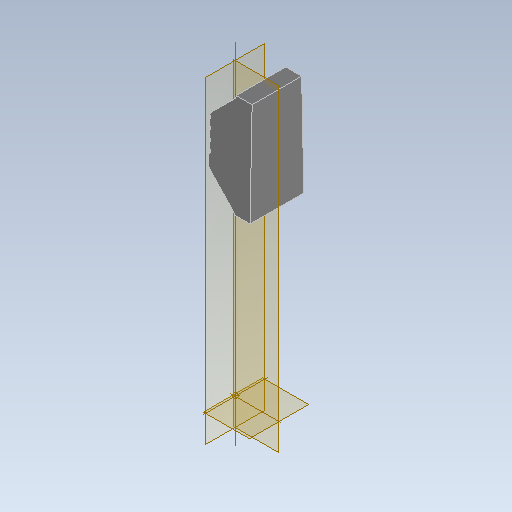
# Autodesk Inventor part: Finger_2
Saved by Autodesk Inventor 2021 (Build 250183000, 183)
## iProperties
Created: 2026-03-26
Part Number: Finger_2
Material: Generic
Document SubType Name: Modeling
Designer: Admin
Density: 1 g/cm^3
Appearance: Silicon Nitride - Polished
Mass: 13.6507 g
Surface Area: 45.9395 cm^2
Volume: 13.6507 cm^3
Author: Admin
Autodesk Inventor part; units mm, degrees
sketch "Sketch1" plane through (0, 0, 0) normal (0, 0, 1) x (1, 0, 0)
  line L0 (0, 0) -> (18, 0)
  line L1 (18, 0) -> (18, 155)
  line L2 (18, 155) -> (0, 155)
  line L3 (0, 155) -> (0, 0)
  dimension "d0" = 155
  dimension "d1" = 18
  constraints: 8 end point, 2 parallel, 1 horizontal, 1 perpendicular
  measures "d0" distance of L2.end L0.start
  measures "d1" distance of L0.start L0.end
extrude "Extrusion1" add sketch "Sketch1" along normal mid plane 25
sketch "Sketch3" plane through (0, 0, 12.5) normal (0, 0, 1) x (1, 0, 0)
  line L0 (18, 155) -> (0, 155) projected
  line L1 (0, 155) -> (0, 135)
  line L2 (0, 135) -> (12, 123)
  line L3 (12, 123) -> (0, 111)
  line L4 (0, 111) -> (0, 91)
  line L5 (0, 155) -> (0, 0) projected
  line L6 (0, 0) -> (18, 0) projected
  line L7 (18, 0) -> (18, 155) projected
  line L8 (18, 0) -> (18, 155)
  line L9 (18, 155) -> (0, 155)
  line L10 (0, 91) -> (12, 79)
  line L11 (12, 79) -> (0, 67)
  line L12 (12, 0) -> (18, 0)
  line L13 (0, 67) -> (0, 47)
  line L14 (0, 47) -> (12, 35)
  line L15 (12, 35) -> (12, 0)
  line L16 (0, 186) -> (0, -31) projected
  line L17 (-3.6, 0) -> (21.6, 0) projected
  dimension "d6" = 20
  dimension "d8" = 20
  dimension "d10" = 20
  dimension "d13" = 12
  dimension "d14" = 12
  dimension "d16" = 12
  dimension "d17" = 135
  dimension "d61" = 135
  dimension "d62" = 135
  dimension "d63" = 135
  dimension "d64" = 135
  constraints: 24 end point, 5 point on line, 4 vertical, 1 collinear, 1 perpendicular, 1 other
  measures "d6" distance of L0.end L1.end
  measures "d8" distance of L3.end L4.end
  measures "d10" distance of L11.end L13.end
  measures "d13" horizontal distance of L2.end L1.end
  measures "d14" distance from line of L5 L10.end
  measures "d16" distance from line of L14.end L13
  measures "d17" angle of L14 L5
  measures "d61" angle of L11 L5
  measures "d62" angle of L3 L5
  measures "d63" angle of L4 L10
  measures "d64" angle of L1 L2
extrude "Extrusion2" cut sketch "Sketch3" against normal through all contours L2 L3 L5 | L6 L5 L14 L15 | L10 L11 L5
sketch "Sketch4" plane through (18, 0, 12.5) normal (1, 0, 0) x (0, 0, -1)
  line L0 (0, 35) -> (25, 35) projected
  line L1 (25, 155) -> (0, 155) projected
  line L2 (2.5, 155) -> (22.5, 155)
  line L3 (25, 35) -> (22.5, 155)
  line L4 (2.5, 155) -> (0, 35)
  line L5 (12.5, -31) -> (12.5, 186) projected
  line L6 (0, 0) -> (0, 155) projected
  line L7 (25, 155) -> (25, 0) projected
  point P0 (12.5, 0)
  point P1 (12.5, 155)
  dimension "d20" = 20
  constraints: 6 end point, 3 point on line, 1 midpoint
  measures "d20" distance of L2.start L2.end
extrude "Extrusion3" cut sketch "Sketch4" against normal through all contours L6 L1 L4 | L3 L1 L7
sketch "Sketch5" plane through (12, 0, -12.5) normal (-1, 0, 0) x (0, 0, 1)
  line L0 (-12, 0) -> (37, 0) projected
  line L1 (12.5, 186) -> (12.5, -31) projected
  line L2 (0, 0) -> (0, 35) projected
  circle A0 centre (0, 20) radius 5
  line L3 (25, 0) -> (25, 35) projected
  circle A1 centre (25, 20) radius 5
  line L4 (25, 35) -> (0, 35) projected
  point P0 (12.5, 0)
  point P1 (25, 25)
  point P2 (25, 15)
  point P3 (0, 25)
  point P4 (0, 15)
  dimension "d58" = 15
  dimension "d59" = 15
  dimension "d60" = 10
  constraints: 2 centre point, 2 point on line, 1 equal radius
  measures "d58" distance from line of A0.centre L4
  measures "d59" distance from line of L4 A1.centre
  measures "d60" diameter of A0
extrude "Extrusion4" cut sketch "Sketch5" against normal through all contours L2 A0 | A1 L3 picked at (1.0391, 18.6969) picked at (24.6011, 18.3818)
fillet "Fillet1" radius 2 8 edges at (12, 79, 0) (0, 91, 0) (0, 111, 0) (12, 123, 0) (0, 135, 0) (0, 67, 0) (12, 35, 0) (0, 47, 0)
sketch "Sketch6" plane through (0, 0, 0) normal (1, 0, 0) x (0, 1, 0)
  line L0 (155, -10) -> (155, 10) projected
  line L1 (-34.6297, 0) -> (207.778, 0) projected
  line L2 (168.0042, -15.8729) -> (152.1314, 0)
  line L3 (152.1314, 0) -> (173.1484, 21.017)
  line L4 (168.0042, -17.0042) -> (151, 0)
  line L5 (151, 0) -> (173.1484, 22.1484)
  line L6 (173.1484, 22.1484) -> (173.1484, 21.017)
  line L7 (168.0042, -17.0042) -> (168.0042, -15.8729)
  line L8 (163.7042, -15.8729) -> (147.8314, 0)
  line L9 (147.8314, 0) -> (168.8484, 21.017)
  line L10 (163.7042, -17.0042) -> (146.7, 0)
  line L11 (146.7, 0) -> (168.8484, 22.1484)
  line L12 (168.8484, 22.1484) -> (168.8484, 21.017)
  line L13 (163.7042, -17.0042) -> (163.7042, -15.8729)
  line L14 (159.4042, -15.8729) -> (143.5314, 0)
  line L15 (143.5314, 0) -> (164.5484, 21.017)
  line L16 (159.4042, -17.0042) -> (142.4, 0)
  line L17 (142.4, 0) -> (164.5484, 22.1484)
  line L18 (164.5484, 22.1484) -> (164.5484, 21.017)
  line L19 (159.4042, -17.0042) -> (159.4042, -15.8729)
  line L20 (155.1042, -15.8729) -> (139.2314, 0)
  line L21 (139.2314, 0) -> (160.2484, 21.017)
  line L22 (155.1042, -17.0042) -> (138.1, 0)
  line L23 (138.1, 0) -> (160.2484, 22.1484)
  line L24 (160.2484, 22.1484) -> (160.2484, 21.017)
  line L25 (155.1042, -17.0042) -> (155.1042, -15.8729)
  line L26 (150.8042, -15.8729) -> (134.9314, 0)
  line L27 (134.9314, 0) -> (155.9484, 21.017)
  line L28 (150.8042, -17.0042) -> (133.8, 0)
  line L29 (133.8, 0) -> (155.9484, 22.1484)
  line L30 (155.9484, 22.1484) -> (155.9484, 21.017)
  line L31 (150.8042, -17.0042) -> (150.8042, -15.8729)
  line L32 (146.5042, -15.8729) -> (130.6314, 0)
  line L33 (130.6314, 0) -> (151.6484, 21.017)
  line L34 (146.5042, -17.0042) -> (129.5, 0)
  line L35 (129.5, 0) -> (151.6484, 22.1484)
  line L36 (151.6484, 22.1484) -> (151.6484, 21.017)
  line L37 (146.5042, -17.0042) -> (146.5042, -15.8729)
  line L38 (94.1, 0) -> (116.2484, 22.1484)
  line L39 (95.2314, 0) -> (116.2484, 21.017)
  line L40 (98.4, 0) -> (120.5484, 22.1484)
  line L41 (99.5314, 0) -> (120.5484, 21.017)
  line L42 (102.7, 0) -> (124.8484, 22.1484)
  line L43 (103.8314, 0) -> (124.8484, 21.017)
  line L44 (124.0042, -15.8729) -> (108.1314, 0)
  line L45 (124.0042, -17.0042) -> (107, 0)
  line L46 (124.0042, -17.0042) -> (124.0042, -15.8729)
  line L47 (115.4042, -17.0042) -> (115.4042, -15.8729)
  line L48 (119.7042, -17.0042) -> (119.7042, -15.8729)
  line L49 (107.6484, 22.1484) -> (107.6484, 21.017)
  line L50 (111.9484, 22.1484) -> (111.9484, 21.017)
  line L51 (89.8, 0) -> (111.9484, 22.1484)
  line L52 (86.6314, 0) -> (107.6484, 21.017)
  line L53 (85.5, 0) -> (107.6484, 22.1484)
  line L54 (90.9314, 0) -> (111.9484, 21.017)
  line L55 (108.1314, 0) -> (129.1484, 21.017)
  line L56 (107, 0) -> (129.1484, 22.1484)
  line L57 (129.1484, 22.1484) -> (129.1484, 21.017)
  line L58 (124.8484, 22.1484) -> (124.8484, 21.017)
  line L59 (120.5484, 22.1484) -> (120.5484, 21.017)
  line L60 (116.2484, 22.1484) -> (116.2484, 21.017)
  line L61 (111.1042, -17.0042) -> (111.1042, -15.8729)
  line L62 (119.7042, -15.8729) -> (103.8314, 0)
  line L63 (119.7042, -17.0042) -> (102.7, 0)
  line L64 (106.8042, -17.0042) -> (106.8042, -15.8729)
  line L65 (115.4042, -15.8729) -> (99.5314, 0)
  line L66 (115.4042, -17.0042) -> (98.4, 0)
  line L67 (102.5042, -17.0042) -> (102.5042, -15.8729)
  line L68 (111.1042, -15.8729) -> (95.2314, 0)
  line L69 (106.8042, -15.8729) -> (90.9314, 0)
  line L70 (106.8042, -17.0042) -> (89.8, 0)
  line L71 (102.5042, -15.8729) -> (86.6314, 0)
  line L72 (102.5042, -17.0042) -> (85.5, 0)
  line L73 (111.1042, -17.0042) -> (94.1, 0)
  line L74 (50.1, 0) -> (72.2484, 22.1484)
  line L75 (51.2314, 0) -> (72.2484, 21.017)
  line L76 (54.4, 0) -> (76.5484, 22.1484)
  line L77 (55.5314, 0) -> (76.5484, 21.017)
  line L78 (58.7, 0) -> (80.8484, 22.1484)
  line L79 (59.8314, 0) -> (80.8484, 21.017)
  line L80 (80.0042, -15.8729) -> (64.1314, 0)
  line L81 (80.0042, -17.0042) -> (63, 0)
  line L82 (80.0042, -17.0042) -> (80.0042, -15.8729)
  line L83 (71.4042, -17.0042) -> (71.4042, -15.8729)
  line L84 (75.7042, -17.0042) -> (75.7042, -15.8729)
  line L85 (63.6484, 22.1484) -> (63.6484, 21.017)
  line L86 (67.9484, 22.1484) -> (67.9484, 21.017)
  line L87 (45.8, 0) -> (67.9484, 22.1484)
  line L88 (42.6314, 0) -> (63.6484, 21.017)
  line L89 (41.5, 0) -> (63.6484, 22.1484)
  line L90 (46.9314, 0) -> (67.9484, 21.017)
  line L91 (64.1314, 0) -> (85.1484, 21.017)
  line L92 (63, 0) -> (85.1484, 22.1484)
  line L93 (85.1484, 22.1484) -> (85.1484, 21.017)
  line L94 (80.8484, 22.1484) -> (80.8484, 21.017)
  line L95 (76.5484, 22.1484) -> (76.5484, 21.017)
  line L96 (72.2484, 22.1484) -> (72.2484, 21.017)
  line L97 (67.1042, -17.0042) -> (67.1042, -15.8729)
  line L98 (75.7042, -15.8729) -> (59.8314, 0)
  line L99 (75.7042, -17.0042) -> (58.7, 0)
  line L100 (62.8042, -17.0042) -> (62.8042, -15.8729)
  line L101 (71.4042, -15.8729) -> (55.5314, 0)
  line L102 (71.4042, -17.0042) -> (54.4, 0)
  line L103 (58.5042, -17.0042) -> (58.5042, -15.8729)
  line L104 (67.1042, -15.8729) -> (51.2314, 0)
  line L105 (62.8042, -15.8729) -> (46.9314, 0)
  line L106 (62.8042, -17.0042) -> (45.8, 0)
  line L107 (58.5042, -15.8729) -> (42.6314, 0)
  line L108 (58.5042, -17.0042) -> (41.5, 0)
  line L109 (67.1042, -17.0042) -> (50.1, 0)
  point P0 (0, 0)
  point P1 (150.7, -10)
  point P2 (150.7, 10)
  point P3 (146.4, -10)
  point P4 (146.4, 10)
  point P5 (142.1, -10)
  point P6 (142.1, 10)
  point P7 (137.8, -10)
  point P8 (137.8, 10)
  point P9 (133.5, -10)
  point P10 (133.5, 10)
  point P11 (111, 10)
  point P12 (106.7, 10)
  point P13 (111, -10)
  point P14 (102.4, 10)
  point P15 (98.1, 10)
  point P16 (93.8, 10)
  point P17 (89.5, 10)
  point P18 (106.7, -10)
  point P19 (102.4, -10)
  point P20 (98.1, -10)
  point P21 (93.8, -10)
  point P22 (89.5, -10)
  point P23 (67, 10)
  point P24 (62.7, 10)
  point P25 (67, -10)
  point P26 (58.4, 10)
  point P27 (54.1, 10)
  point P28 (49.8, 10)
  point P29 (45.5, 10)
  point P30 (62.7, -10)
  point P31 (58.4, -10)
  point P32 (54.1, -10)
  point P33 (49.8, -10)
  point P34 (45.5, -10)
  point P35 (155, 4)
  point P36 (155, -4)
  point P37 (155, -2.8686)
  point P38 (155, 2.8686)
  dimension "d29" = 0.8
  dimension "d30" = 4
  dimension "d31" = 45
  dimension "d32" = 45
  dimension "d35" = 4.3
  dimension "d42" = 44
  constraints: 216 end point, 2 horizontal, 2 parallel, 2 point on line, 2 vertical, 238 other
  measures "d29" distance between parallel lines of L4 L2
  measures "d30" distance from line of L0 L4.end
  measures "d31" angle of L1 L2
  measures "d32" angle of L3 L1
  measures "d35" distance of L0.start point (150.7, -10)
  measures "d42" distance of L0.end point (111, 10)
extrude "Extrusion5" cut sketch "Sketch6" along normal blind 0.5 contours L10 L1 L8 L0 | L0 L8 L13 L10 | L11 L0 L9 L1 | L4 L1 L2 L0 | L11 L12 L9 L0 | L5 L0 L3 L1 | L89 L85 L88 L1 | L1 L107 L103 L108 | L87 L86 L90 L1 | L1 L105 L100 L106 | L74 L96 L75 L1 | L1 L104 L97 L109 | L76 L95 L77 L1 | L1 L101 L83 L102 | L78 L94 L79 L1 | L1 L98 L84 L99 | L92 L93 L91 L1 | L1 L80 L82 L81 | L53 L49 L52 L1 | L1 L71 L67 L72 | L51 L50 L54 L1 | L1 L69 L64 L70 | L38 L60 L39 L1 | L1 L68 L61 L73 | L40 L59 L41 L1 | L1 L65 L47 L66 | L42 L58 L43 L1 | L1 L62 L48 L63 | L56 L57 L55 L1 | L1 L44 L46 L45 | L35 L36 L33 L1 | L1 L32 L37 L34 | L29 L30 L27 L1 | L1 L26 L31 L28 | L23 L24 L21 L1 | L1 L20 L25 L22 | L17 L18 L15 L1 | L1 L14 L19 L16
fillet "Fillet2" radius 5 2 edges at (9, 155, -10) (9, 155, 10)
sketch "Sketch9" plane through (0, 0, 0) normal (0, 1, 0) x (-1, 0, 0)
  line L0 (-3.9523, 0) -> (14.2412, 0)
  line L1 (20.6894, 0) -> (-24.4482, 0) projected
  circle A0 centre (-6, -4.5) radius 1.9
  line L2 (-18, 12.5) -> (-18, -12.5) projected
  line L3 (0, -17.5) -> (0, 17.5) projected
  circle A1 centre (-6, 4.5) radius 1.9
  point P0 (0, 0)
  point P1 (5.1445, 0)
  dimension "d65" = 3.8
  dimension "d66" = 4.5
  dimension "d68" = 6
  constraints: 2 centre point, 2 end point, 1 horizontal, 1 midpoint, 1 point on line, 1 symmetric about line, 1 other
  measures "d65" diameter of A0
  measures "d66" distance from line of L1 A0.centre
  measures "d68" distance from line of L3 A0.centre
extrude "Extrusion7" cut sketch "Sketch9" along normal blind 141.25
sketch "Sketch10" plane through (0, 0, 0) normal (0, 0, 1) x (1, 0, 0)
  line L0 (25.8962, 159.5888) -> (-5.6223, 159.5888)
  line L1 (-5.6223, 159.5888) -> (-5.6223, 123)
  line L2 (-5.6223, 123) -> (25.8962, 123)
  line L3 (25.8962, 123) -> (25.8962, 159.5888)
  line L4 (31.4798, 79) -> (-28.9871, 79)
  line L5 (-28.9871, 79) -> (-28.9871, -29.2259)
  line L6 (-28.9871, -29.2259) -> (31.4798, -29.2259)
  line L7 (31.4798, -29.2259) -> (31.4798, 79)
  constraints: 16 end point, 4 parallel, 2 horizontal, 2 perpendicular
extrude "Extrusion8" cut sketch "Sketch10" against normal through all both and the other way through all
body "Solid1"
